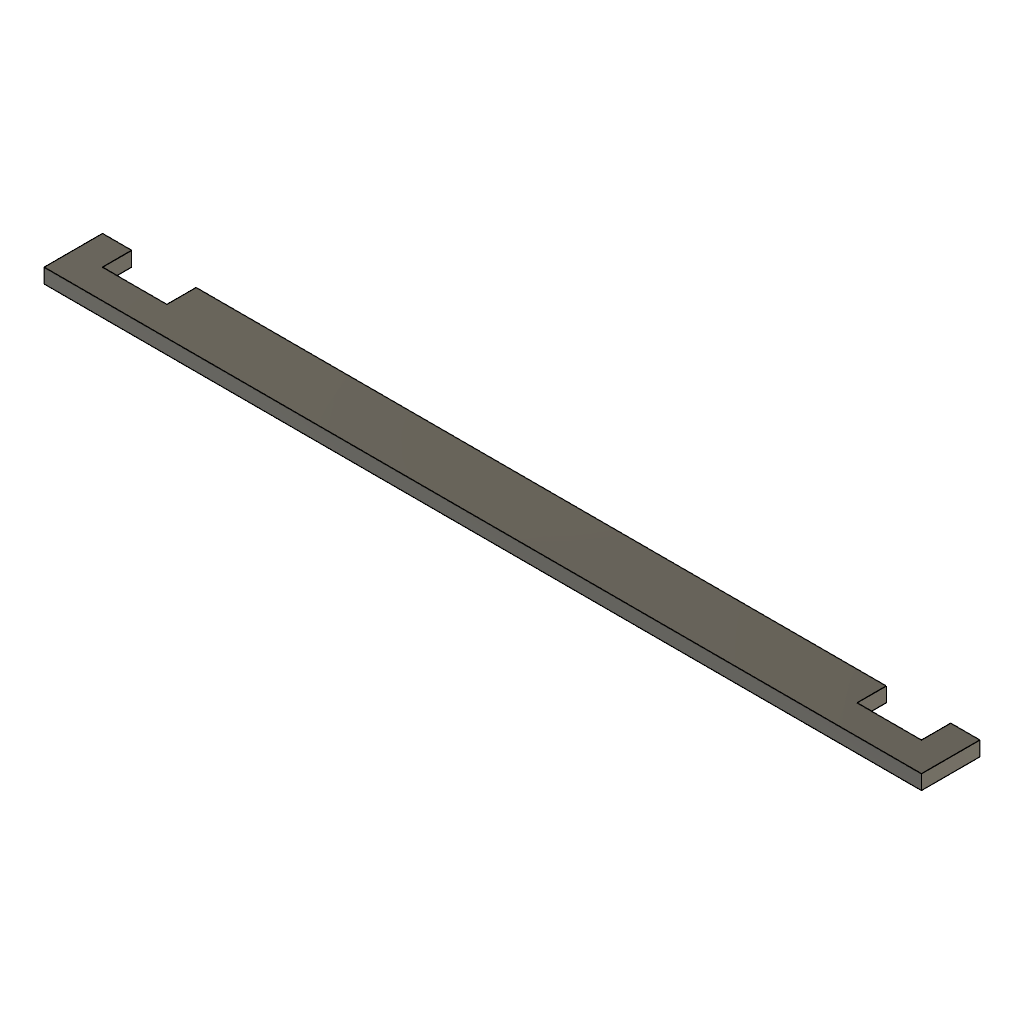
Barra_lateral (Autodesk Fusion 360 design; units mm, degrees)
part number: 2026-09-25-16-38-31-451
Autodesk Fusion 360 part; units mm, degrees
sketch "Boceto1" plane through (0, 0, 0) normal (0, 0, 1) x (1, 0, 0)
  line L0 (0, 0) -> (300, 0)
  line L1 (300, 0) -> (300, 20)
  line L2 (300, 20) -> (0, 20)
  line L3 (0, 20) -> (0, 0)
  line L4 (10, 20) -> (32, 20)
  line L5 (32, 20) -> (32, 10)
  line L6 (32, 10) -> (10, 10)
  line L7 (10, 10) -> (10, 20)
  line L8 (290, 20) -> (268, 20)
  line L9 (268, 20) -> (268, 10)
  line L10 (268, 10) -> (290, 10)
  line L11 (290, 10) -> (290, 20)
  dimension "d1" = 300
  dimension "d2" = 20
  dimension "d3" = 22
  dimension "d4" = 10
  dimension "d5" = 22
  dimension "d6" = 10
  dimension "d7" = 10
  dimension "d8" = 10
  constraint horizontal L0
  constraint vertical L1
  constraint horizontal L2
  constraint vertical L3
  constraint coincident L0.start L3.end
  constraint horizontal L4
  constraint vertical L5
  constraint horizontal L6
  constraint vertical L7
  constraint coincident L2 L4.start
  constraint horizontal L8
  constraint vertical L9
  constraint horizontal L10
  constraint vertical L11
  constraint coincident L2 L8.start
  measures "d1" distance of L0.start L0.end
  measures "d2" distance of L0.end L1.end
  measures "d3" distance of L5.end L6.end
  measures "d4" distance of L3 L7
  measures "d5" distance of L9.end L10.end
  measures "d6" distance of L1 L11
  measures "d7" distance of L4.end L5.end
  measures "d8" distance of L8.end L9.end
extrude "Extruir1" add sketch "Boceto1" along normal blind 5 contours L0 L1 L2 L3 L5 L6 L7 L9 L10 L11
